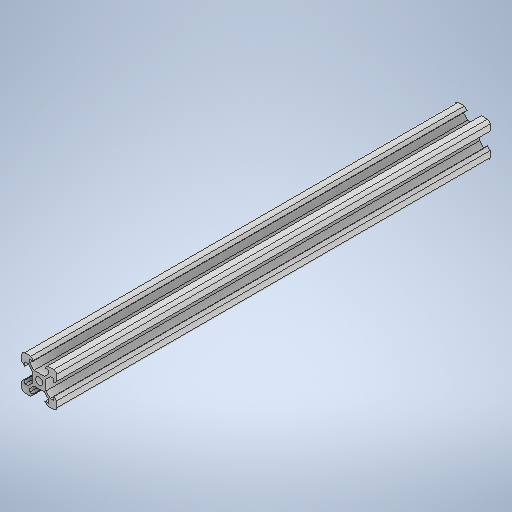
# Autodesk Inventor part: Perfil_250
Saved by Autodesk Inventor 2025.3 (Build 293356030, 356C)
## iProperties
Created: 2026-02-26
Part Number: Perfil_250
Material: Generic
Document SubType Name: Modeling
Designer: pablo
Density: 1 g/cm^3
Appearance: Default
Author: pablo
Autodesk Inventor part; units mm, degrees
ref_plane "YZ Plane" through (0, 0, 0) normal (1, 0, 0) x (0, 1, 0)
ref_plane "XZ Plane" through (0, 0, 0) normal (0, 1, 0) x (-1, 0, 0)
ref_plane "XY Plane" through (0, 0, 0) normal (0, 0, 1) x (1, 0, 0)
sketch "Sketch1" plane through (0, 0, 0) normal (0, 0, 1) x (1, 0, 0)
  circle A0 centre (0, 0) radius 2.1
  line L0 (10, 10) -> (10, -10)
  line L1 (10, -10) -> (-10, -10)
  line L2 (-10, -10) -> (-10, 10)
  line L3 (4.85, 10) -> (3.05, 8.2)
  line L4 (-4.85, 10) -> (-3.05, 8.2)
  line L5 (-3.05, 8.2) -> (-5.5, 8.2)
  line L6 (-5.5, 8.2) -> (-5.5, 6.4456)
  line L7 (-2.9544, 3.9) -> (2.9544, 3.9)
  line L8 (5.5, 6.4456) -> (5.5, 8.2)
  line L9 (5.5, 8.2) -> (3.05, 8.2)
  line L10 (0, -10.0033) -> (0, -10) construction
  line L11 (-10, 0) -> (10, 0) construction
  line L12 (-10, 10) -> (-4.85, 10)
  line L13 (4.85, 10) -> (10, 10)
  line L14 (0, 0) -> (0, 3.9) construction
  line L15 (2.9544, 3.9) -> (5.5, 6.4456)
  line L16 (-2.9544, 3.9) -> (-5.5, 6.4456)
  line L17 (-4.85, -10) -> (-3.05, -8.2)
  line L18 (-3.05, -8.2) -> (-5.5, -8.2)
  line L19 (-2.9544, -3.9) -> (-5.5, -6.4456)
  line L20 (-5.5, -8.2) -> (-5.5, -6.4456)
  line L21 (-2.9544, -3.9) -> (2.9544, -3.9)
  line L22 (0, 0) -> (0, -3.9) construction
  line L23 (2.9544, -3.9) -> (5.5, -6.4456)
  line L24 (5.5, -6.4456) -> (5.5, -8.2)
  line L25 (5.5, -8.2) -> (3.05, -8.2)
  line L26 (4.85, -10) -> (3.05, -8.2)
  line L27 (-10, 4.85) -> (-8.2, 3.05)
  line L28 (-8.2, 3.05) -> (-8.2, 5.5)
  line L29 (-8.2, 5.5) -> (-6.4456, 5.5)
  line L30 (-6.4456, 5.5) -> (-3.9, 2.9544)
  line L31 (-3.9, 2.9544) -> (-3.9, -2.9544)
  line L32 (-3.9, -2.9544) -> (-6.4456, -5.5)
  line L33 (-6.4456, -5.5) -> (-8.2, -5.5)
  line L34 (-8.2, -5.5) -> (-8.2, -3.05)
  line L35 (-8.2, -3.05) -> (-10, -4.85)
  line L36 (10, 4.85) -> (8.2, 3.05)
  line L37 (8.2, 3.05) -> (8.2, 5.5)
  line L38 (8.2, 5.5) -> (6.4456, 5.5)
  line L39 (6.4456, 5.5) -> (3.9, 2.9544)
  line L40 (3.9, 2.9544) -> (3.9, -2.9544)
  line L41 (3.9, -2.9544) -> (6.4456, -5.5)
  line L42 (6.4456, -5.5) -> (8.2, -5.5)
  line L43 (8.2, -5.5) -> (8.2, -3.05)
  line L44 (8.2, -3.05) -> (10, -4.85)
  point P0 (0, -10.0016)
  point P1 (-3.9, 0)
  dimension "d0" = 4.2
  dimension "d1" = 20
  dimension "d2" = 20
  dimension "d3" = 90
  dimension "d4" = 6.1
  dimension "d5" = 11
  dimension "d6" = 1.8
  dimension "d7" = 6.1
  dimension "d8" = 1.8
  dimension "d9" = 45
  dimension "d10" = 45
  dimension "d11" = 1.8
  dimension "d12" = 6.1
  dimension "d13" = 6.1
  dimension "d14" = 11
  dimension "d15" = 3.6
  dimension "d16" = 3.6
  constraints: 90 end point, 21 symmetric about line, 11 perpendicular, 8 point on line, 7 midpoint, 6 equal length, 5 parallel, 3 horizontal, 3 vertical alignment, 2 coincident, 2 horizontal alignment, 2 vertical, 1 centre point
  measures "d0" diameter of A0
  measures "d1" distance of L2.end L0.start
  measures "d2" distance of L0.start L1.start
  measures "d3" angle of L4 L3
  measures "d4" distance of L3.end L4.end
  measures "d5" distance between parallel lines of L6 L8
  measures "d6" distance between parallel lines of L13 L9
  measures "d7" distance between parallel lines of L13 L7
  measures "d8" distance between parallel lines of L12 L5
  measures "d9" angle of L14 L15
  measures "d10" angle of L14 L16
  measures "d11" distance between parallel lines of L2 L28
  measures "d12" distance of L35.start L28.start
  measures "d13" distance between parallel lines of L2 L31
  measures "d14" distance between parallel lines of L29 L33
  measures "d15" distance of L7.end L15.end
  measures "d16" distance of L30.start L31.start
extrude "Extrusion1" add sketch "Sketch1" along normal blind 250 contours L0 L36 L37 L38 L39 L40 L41 L42 L43 L44 L1 L26 L25 L24 L23 L21 L19 L20 L18 L17 L2 L35 L34 L33 L32 L31 L30 L29 L28 L27 L12 L4 L5 L6 L16 L7 L15 L8 L9 L3 L13
fillet "Fillet1" radius 1.6 4 edges at (10, 10, 125) (-10, 10, 125) (10, -10, 125) (-10, -10, 125)
fillet "Fillet2" radius 0.2 8 edges at (-3.05, -8.2, 125) (-8.2, -3.05, 125) (-8.2, 3.05, 125) (-3.05, 8.2, 125) (3.05, 8.2, 125) (8.2, 3.05, 125) (8.2, -3.05, 125) (3.05, -8.2, 125)
body "Solid1"
